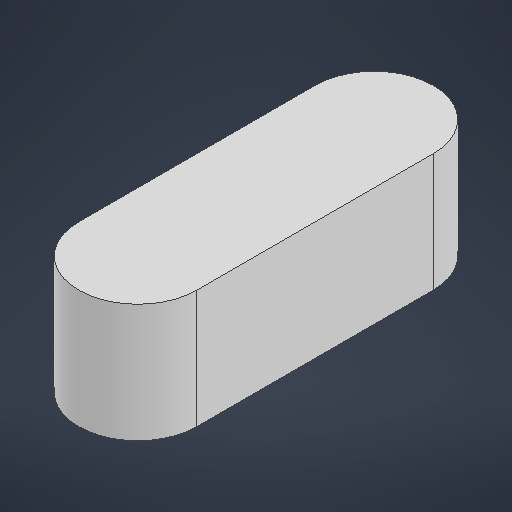
# Autodesk Inventor part: Chaveta
Saved by Autodesk Inventor 2026.2 (Build 302298000, 298)
## iProperties
Created: 2026-10-16
Part Number: Chaveta
Material: Genérico
Document SubType Name: Modeling
Designer: IFSP
Density: 1 g/cm^3
Appearance: Padrão
Author: IFSP
Autodesk Inventor part; units mm, degrees
ref_plane "YZ Plane" through (0, 0, 0) normal (1, 0, 0) x (0, 1, 0)
ref_plane "XZ Plane" through (0, 0, 0) normal (0, 1, 0) x (-1, 0, 0)
ref_plane "XY Plane" through (0, 0, 0) normal (0, 0, 1) x (1, 0, 0)
sketch "Esboço1" plane through (0, 0, 0) normal (0, 1, 0) x (-1, 0, 0)
  line L0 (0, 25.3148) -> (0, 19.3148) construction
  line L1 (-1.5, 25.3148) -> (-1.5, 19.3148)
  line L2 (1.5, 19.3148) -> (1.5, 25.3148)
  arc A0 (1.5, 25.3148) -> (-1.5, 25.3148) centre (0, 25.3148) ccw
  arc A1 (-1.5, 19.3148) -> (1.5, 19.3148) centre (0, 19.3148) ccw
  point P0 (0, 0)
  point P1 (0, 22.3148)
  dimension "d0" = 6
  dimension "d1" = 3
  constraints: 8 end point, 4 point on circle, 4 tangent, 2 centre point, 1 midpoint, 1 parallel, 1 vertical
  measures "d0" distance of L0.start L0.end
  measures "d1" diameter of A1
extrude "Extrusão1" add sketch "Esboço1" along normal blind 3
